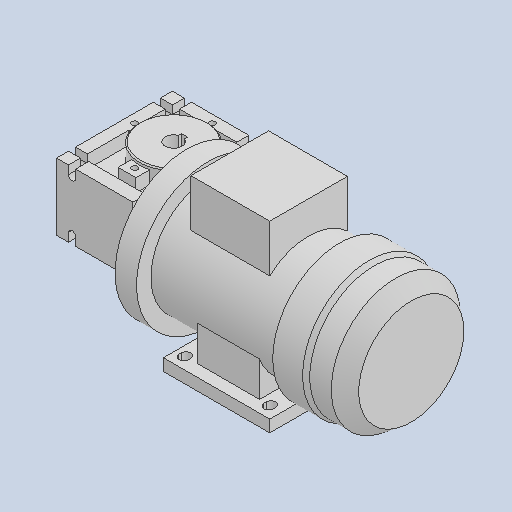
# Autodesk Inventor part: RDS-5005 Gear Motor
Saved by Autodesk Inventor 2026.2 (Build 302298000, 298)
## iProperties
Created: 2024-04-02
Part Number: RDS-5005 Gear Motor
Material: Типовые
Document SubType Name: Modeling
Designer: pokla
Density: 1 g/cm^3
Appearance: По умолчанию
Stock Number: Мотор-редуктор (СДР 060 2.0)
Author: pokla
Autodesk Inventor part; units mm, degrees
ref_plane "YZ Plane" through (0, 0, 0) normal (1, 0, 0) x (0, 1, 0)
sketch "Эскиз1" plane through (0, 0, 0) normal (0, 1, 0) x (-1, 0, 0)
  line L0 (0, 0) -> (0, -60)
  line L1 (0, -60) -> (-18, -60)
  line L2 (-18, -60) -> (-18, -48)
  line L3 (-18, -48) -> (-128, -48)
  line L4 (-128, -48) -> (-128, -56)
  line L5 (-128, -56) -> (-153, -56)
  line L6 (-175, -54) -> (-188, -44)
  line L7 (-188, -44) -> (-188, 0)
  line L8 (-188, 0) -> (0, 0)
  line L9 (-153, -56) -> (-157, -54)
  line L10 (-157, -54) -> (-175, -54)
  point P0 (-9, -60)
  dimension "d0" = 188
  dimension "d1" = 18
  dimension "d2" = 12
  dimension "d3" = 110
  dimension "d4" = 25
  dimension "d6" = 2
  dimension "d7" = 4
  dimension "d8" = 18
  dimension "d10" = 10
  dimension "d13" = 8
  dimension "d14" = 120
  constraints: 22 end point, 6 perpendicular, 1 horizontal, 1 midpoint, 1 parallel, 1 vertical
  measures "d0" distance of L7.end L0.start
  measures "d1" distance of L0.end L1.end
  measures "d2" distance of L1.end L2.end
  measures "d3" distance of L2.end L3.end
  measures "d4" distance of L4.end L5.end
  measures "d6" vertical distance of L5.end L9.end
  measures "d7" horizontal distance of L5.end L9.end
  measures "d8" distance of L9.end L6.start
  measures "d10" vertical distance of L6.start L6.end
  measures "d13" distance of L3.end L4.end
  measures "d14" diameter of point (-9, -60) L8
revolve "Вращение1" add sketch "Эскиз1" angle 360 about axis through (188, 0, 0) along (-1, 0, 0)
sketch "Эскиз2" plane through (0, 0, 0) normal (0, 1, 0) x (-1, 0, 0)
  line L0 (-18, -48) -> (-18, 48) projected
  line L1 (-128, -48) -> (-128, 48) projected
  line L2 (-54, -45) -> (-106, -45)
  line L3 (-106, -45) -> (-106, 45)
  line L4 (-106, 45) -> (-54, 45)
  line L5 (-54, 45) -> (-54, -45)
  point P0 (0, 0)
  point P1 (-54, 0)
  point P2 (-18, 0)
  dimension "d16" = 52
  dimension "d17" = 90
  dimension "d18" = 36
  constraints: 8 end point, 2 midpoint, 2 parallel, 1 horizontal, 1 horizontal alignment, 1 perpendicular
  measures "d16" distance of L3.end L4.end
  measures "d17" distance of L2.end L3.end
  measures "d18" distance between parallel lines of L5 L0
extrude "Выдавливание1" add sketch "Эскиз2" against normal blind 46
sketch "Эскиз3" plane through (0, -46, 0) normal (0, -1, 0) x (1, 0, 0)
  line L0 (35.5, 55) -> (124.5, 55)
  line L1 (124.5, 55) -> (124.5, -55)
  line L2 (124.5, -55) -> (35.5, -55)
  line L3 (35.5, -55) -> (35.5, 55)
  line L4 (54, -45) -> (106, -45) projected
  point P0 (0, 0)
  point P1 (124.5, 0)
  point P2 (80, -55)
  point P3 (80, -45)
  dimension "d21" = 89
  dimension "d22" = 110
  constraints: 8 end point, 3 midpoint, 2 parallel, 1 horizontal, 1 horizontal alignment, 1 perpendicular, 1 vertical alignment
  measures "d21" distance of L1.end L2.end
  measures "d22" distance of L0.end L1.end
extrude "Выдавливание2" add sketch "Эскиз3" along normal blind 10
sketch "Эскиз4" plane through (0, -56, 0) normal (0, -1, 0) x (1, 0, 0)
  line L0 (43.5, 46) -> (43.5, 44) construction
  line L1 (39.5, 46) -> (39.5, 44)
  line L2 (47.5, 44) -> (47.5, 46)
  arc A0 (47.5, 46) -> (39.5, 46) centre (43.5, 46) ccw
  arc A1 (39.5, 44) -> (47.5, 44) centre (43.5, 44) ccw
  line L3 (35.5, 55) -> (35.5, -55) projected
  line L4 (124.5, 55) -> (35.5, 55) projected
  point P0 (0, 0)
  point P1 (43.5, 45)
  point P2 (43.5, 40)
  point P3 (43.5, 50)
  point P4 (47.5, 45)
  point P5 (39.5, 45)
  dimension "d25" = 12
  dimension "d27" = 10
  dimension "d28" = 15
  dimension "d29" = 8
  constraints: 8 end point, 6 point on circle, 4 tangent, 3 midpoint, 2 centre point, 1 parallel
  measures "d25" distance between parallel lines of L3 L2
  measures "d27" distance of point (43.5, 40) point (43.5, 50)
  measures "d28" distance from line of L4 point (43.5, 40)
  measures "d29" distance of point (47.5, 45) point (39.5, 45)
extrude "Выдавливание3" cut sketch "Эскиз4" against normal blind 10
pattern_linear "Прямоуг.массив1" count 2 spacing 90 along (0, 0, -1) count 2 spacing 71 along (1, 0, 0) of "Выдавливание3"
sketch "Эскиз5" plane through (0, 0, 0) normal (0, 1, 0) x (-1, 0, 0)
  line L0 (-128, -48) -> (-128, 48) projected
  line L1 (-18, -48) -> (-18, 48) projected
  line L2 (-54, -13.7113) -> (-35.5, -13.7113) projected
  line L3 (-35.5, -13.7113) -> (-35.5, 13.7113) projected
  line L4 (-35.5, 13.7113) -> (-54, 13.7113) projected
  line L5 (-54, 13.7113) -> (-54, 45) projected
  line L6 (-54, 45) -> (-106, 45) projected
  line L7 (-106, 45) -> (-106, 13.7113) projected
  line L8 (-106, 13.7113) -> (-124.5, 13.7113) projected
  line L9 (-124.5, 13.7113) -> (-124.5, -13.7113) projected
  line L10 (-124.5, -13.7113) -> (-106, -13.7113) projected
  line L11 (-106, -13.7113) -> (-106, -45) projected
  line L12 (-106, -45) -> (-54, -45) projected
  line L13 (-54, -45) -> (-54, -13.7113) projected
  line L14 (-36, -32.5) -> (-102, -32.5)
  line L15 (-102, -32.5) -> (-102, 32.5)
  line L16 (-102, 32.5) -> (-36, 32.5)
  line L17 (-36, 32.5) -> (-36, -32.5)
  point P0 (0, 0)
  point P1 (-36, 0)
  point P2 (-18, 0)
  dimension "d38" = 66
  dimension "d39" = 65
  dimension "d40" = 18
  constraints: 8 end point, 2 midpoint, 2 parallel, 1 horizontal, 1 horizontal alignment, 1 perpendicular
  measures "d38" distance of L15.end L16.end
  measures "d39" distance of L14.end L15.end
  measures "d40" distance between parallel lines of L1 L17
extrude "Выдавливание4" add sketch "Эскиз5" along normal blind 75 contours L13 L14 L15 L16 L5 L4 L17 L2 | L2 L17 L14 L13 | L4 L5 L16 L17
sketch "Эскиз6" plane through (0, 0, 0) normal (1, 0, 0) x (0, 1, 0)
  line L0 (-28, 29) -> (-28, -68)
  line L1 (-28, -68) -> (28, -68)
  line L2 (28, -68) -> (28, 29)
  line L3 (28, 29) -> (-28, 29)
  line L4 (0, 0) -> (0, 234.4488) construction
  line L5 (0, 0) -> (0, -194.3934) construction
  point P0 (0, 29)
  point P1 (0, -68)
  dimension "d45" = 97
  dimension "d46" = 56
  dimension "d47" = 180
  dimension "d48" = 29
  constraints: 12 end point, 2 midpoint, 2 parallel, 2 point on line, 1 perpendicular, 1 vertical
  measures "d45" distance of L0.start L0.end
  measures "d46" distance of L1.end L0.end
  measures "d47" angle of L4 L5
  measures "d48" distance of L4.start point (0, 29)
extrude "Выдавливание5" add sketch "Эскиз6" against normal blind 80
ref_plane "РабПлоскость1" through (-80, -28, -19.5) normal (0, 0, -1) x (1, 0, 0)
sketch "Эскиз7" plane through (-80, -28, -68) normal (0, 0, -1) x (1, 0, 0)
  line L0 (80, 0) -> (80, -56) projected
  line L1 (80, 0) -> (0, 0) projected
  line L2 (0, -56) -> (0, 0) projected
  line L3 (80, -56) -> (0, -56) projected
  line L4 (10, 0) -> (10, -7)
  arc A0 (10, -7) -> (16, -7) centre (13, -7) ccw
  line L5 (16, -7) -> (16, 0)
  line L6 (80, -56) -> (0, -56) projected
  line L7 (40, 0) -> (40, -56) construction
  line L8 (0, -28) -> (80, -28) construction
  line L9 (80, 32) -> (80, -88) construction
  line L10 (70, 0) -> (70, -7)
  arc A1 (64, -7) -> (70, -7) centre (67, -7) ccw
  line L11 (64, -7) -> (64, 0)
  line L12 (10, -56) -> (10, -49)
  arc A2 (16, -49) -> (10, -49) centre (13, -49) ccw
  line L13 (16, -49) -> (16, -56)
  line L14 (70, -56) -> (70, -49)
  arc A3 (70, -49) -> (64, -49) centre (67, -49) ccw
  line L15 (64, -49) -> (64, -56)
  point P0 (13, -10)
  point P1 (67, -10)
  point P2 (13, -46)
  point P3 (67, -46)
  point P4 (16, -56)
  point P5 (64, 0)
  dimension "d51" = 6
  dimension "d52" = 10
  dimension "d53" = 10
  constraints: 20 end point, 18 symmetric about line, 9 point on circle, 4 centre point, 3 midpoint, 3 perpendicular, 2 point on line, 2 tangent, 3 other
  measures "d51" distance between parallel lines of L5 L4
  measures "d52" distance from line of L1 point (13, -10)
  measures "d53" distance between parallel lines of L2 L4
extrude "Выдавливание6" cut sketch "Эскиз7" against normal blind 11 contours L10 A1 L11 L1 | L3 L15 A3 L14 | L5 A0 L4 L1 | L3 L12 A2 L13
sketch "Эскиз8" plane through (-80, 0, 0) normal (-1, 0, 0) x (0, 0, 1)
  line L0 (-68, 28) -> (-68, -28) projected
  line L1 (-68, -28) -> (29, -28) projected
  line L2 (29, -28) -> (29, 28) projected
  line L3 (29, 28) -> (-68, 28) projected
  line L4 (-58, -28) -> (-58, -21)
  arc A0 (-52, -21) -> (-58, -21) centre (-55, -21) ccw
  line L5 (-52, -21) -> (-52, -28)
  line L6 (-68, 0) -> (29, 0) construction
  line L7 (-19.5, 28) -> (-19.5, -28) construction
  line L8 (-58, 28) -> (-58, 21)
  arc A1 (-58, 21) -> (-52, 21) centre (-55, 21) ccw
  line L9 (-52, 21) -> (-52, 28)
  line L10 (19, -28) -> (19, -21)
  arc A2 (19, -21) -> (13, -21) centre (16, -21) ccw
  line L11 (13, -21) -> (13, -28)
  line L12 (19, 28) -> (19, 21)
  arc A3 (13, 21) -> (19, 21) centre (16, 21) ccw
  line L13 (13, 21) -> (13, 28)
  point P0 (0, 0)
  point P1 (-55, -18)
  point P2 (-55, 18)
  point P3 (16, -18)
  point P4 (16, 18)
  point P5 (19, 28)
  point P6 (13, 28)
  point P7 (-52, 28)
  point P8 (-58, 28)
  point P9 (13, -28)
  point P10 (19, -28)
  dimension "d56" = 10
  dimension "d57" = 6
  dimension "d58" = 10
  constraints: 20 end point, 18 symmetric about line, 9 point on circle, 4 centre point, 4 midpoint, 2 perpendicular, 2 point on line, 2 tangent, 3 other
  measures "d56" distance between parallel lines of L0 L4
  measures "d57" distance between parallel lines of L4 L5
  measures "d58" distance from line of L1 point (-55, -18)
extrude "Выдавливание7" cut sketch "Эскиз8" against normal blind 11 contours L3 L9 A1 L8 | L4 A0 L5 L1 | L3 L12 A3 L13 | L11 A2 L10 L1
mirror "Зеркальное отражение1" about plane through (-80, -28, -19.5) normal (0, 0, -1) of "Выдавливание6"
sketch "Эскиз9" plane through (0, 0, 0) normal (1, 0, 0) x (0, 0, -1)
  line L0 (58, -28) -> (58, -21) projected
  arc A0 (58, -21) -> (52, -21) centre (55, -21) ccw projected
  line L1 (52, -21) -> (52, -28) projected
  line L2 (58, 21) -> (58, 28) projected
  arc A1 (52, 21) -> (58, 21) centre (55, 21) ccw projected
  line L3 (52, 28) -> (52, 21) projected
  line L4 (58, -28) -> (52, -28)
  line L5 (68, -28) -> (57, -28) projected
  line L6 (52, 28) -> (52, 21) projected
  line L7 (58, 28) -> (52, 28)
  point P0 (0, 0)
  constraints: 4 end point, 1 collinear, 1 perpendicular
extrude "Выдавливание8" cut sketch "Эскиз9" against normal blind 11
sketch "Эскиз10" plane through (-64, -28, -68) normal (0, -1, 0) x (1, 0, 0)
  circle A0 centre (24, 39) radius 7
  line L0 (48, 97) -> (0, 97) construction
  line L1 (24, 97) -> (24, 0) construction
  line L2 (48, 0) -> (0, 0) construction
  line L3 (48, 97) -> (0, 97) construction
  line L4 (48, 0) -> (0, 0) construction
  point P0 (64, 68)
  point P1 (24, 97)
  point P2 (24, 0)
  dimension "d63" = 14
  dimension "d64" = 39
  constraints: 4 midpoint, 2 end point, 1 centre point, 1 vertical alignment
  measures "d63" diameter of A0
  measures "d64" distance of point (24, 0) A0.centre
extrude "Выдавливание9" cut sketch "Эскиз10" against normal up to surface (56 mm away)
sketch "Эскиз11" plane through (-64, -28, -68) normal (0, -1, 0) x (1, 0, 0)
  circle A0 centre (24, 39) radius 7 projected
  circle A1 centre (24, 39) radius 28.5
  point P0 (64, 68)
  dimension "d67" = 57
  constraints: 1 centre point, 1 coincident
  measures "d67" diameter of A1
extrude "Выдавливание10" add sketch "Эскиз11" along normal blind 3
sketch "Эскиз12" plane through (-64, -28, -68) normal (0, -1, 0) x (1, 0, 0)
  circle A0 centre (24, 39) radius 28.5 projected
  circle A1 centre (24, 39) radius 28.5 projected
  line L0 (53, 11) -> (53, 16) projected
  line L1 (53, 16) -> (64, 16) projected
  line L2 (64, 97) -> (64, 16) projected
  line L3 (64, 97) -> (54, 97) projected
  line L4 (54, 97) -> (54, 86) projected
  line L5 (54, 86) -> (48, 86) projected
  line L6 (48, 86) -> (48, 97) projected
  line L7 (48, 97) -> (0, 97) projected
  line L8 (0, 97) -> (0, 86) projected
  line L9 (0, 86) -> (-5, 86) projected
  line L10 (-5, 86) -> (-5, 81) projected
  line L11 (-5, 81) -> (-16, 81) projected
  line L12 (-16, 16) -> (-16, 81) projected
  line L13 (-16, 16) -> (-5, 16) projected
  line L14 (-5, 16) -> (-5, 11) projected
  line L15 (-5, 11) -> (0, 11) projected
  line L16 (0, 11) -> (0, 0) projected
  line L17 (48, 0) -> (0, 0) projected
  line L18 (48, 0) -> (48, 11) projected
  line L19 (48, 11) -> (53, 11) projected
  line L20 (31.5, 78) -> (31.5, 0)
  line L21 (31.5, 0) -> (16.5, 0)
  line L22 (16.5, 0) -> (16.5, 78)
  line L23 (16.5, 78) -> (31.5, 78)
  line L24 (31.5, 78) -> (16.5, 0) construction
  line L25 (31.5, 0) -> (16.5, 78) construction
  line L26 (24, 78) -> (24, 0) construction
  line L27 (64, 31.5) -> (-16, 31.5)
  line L28 (-16, 31.5) -> (-16, 46.5)
  line L29 (-16, 46.5) -> (64, 46.5)
  line L30 (64, 46.5) -> (64, 31.5)
  line L31 (64, 31.5) -> (-16, 46.5) construction
  line L32 (-16, 31.5) -> (64, 46.5) construction
  line L33 (64, 39) -> (-16, 39) construction
  line L34 (-6, 87) -> (-16, 87) projected
  line L35 (-6, 87) -> (-6, 10)
  line L36 (54, 10) -> (53, 11) projected
  line L37 (-6, 10) -> (54, 10)
  line L38 (54, 10) -> (54, 86)
  line L39 (54, 86) -> (-6, 86)
  point P0 (64, 68)
  point P1 (24, 39)
  point P2 (24, 39)
  point P3 (0, 10)
  point P4 (16.5, 10)
  point P5 (16.5, 11.5045)
  point P6 (-3.4955, 31.5)
  point P7 (-6, 31.5)
  point P8 (-6, 16)
  point P9 (54, 16)
  point P10 (54, 31.5)
  point P11 (51.4955, 31.5)
  point P12 (31.5, 11.5045)
  point P13 (31.5, 10)
  point P14 (48, 10)
  point P15 (31.5, 66.4955)
  point P16 (51.4955, 46.5)
  point P17 (54, 46.5)
  point P18 (48, 86)
  point P19 (0, 86)
  point P20 (-6, 81)
  point P21 (-6, 46.5)
  point P22 (-3.4955, 46.5)
  point P23 (16.5, 66.4955)
  dimension "d72" = 78
  dimension "d73" = 15
  dimension "d74" = 80
  dimension "d75" = 15
  constraints: 36 end point, 7 midpoint, 5 perpendicular, 4 parallel, 1 coincident, 1 horizontal, 1 point on line, 1 vertical, 1 other
  measures "d72" distance of L20.start L20.end
  measures "d73" distance of L20.end L21.end
  measures "d74" distance of L27.start L27.end
  measures "d75" distance of L27.end L28.end
extrude "Выдавливание11" cut sketch "Эскиз12" against normal blind 11 contours A0 L20 L23 L22 L29 L35 L11 L10 L9 L39 L5 L38 | L27 L38 L1 L0 L19 L18 L37 L20 A0 | L22 L37 L16 L15 L14 L13 L35 L27 A0
ref_plane "РабПлоскость2" through (-64, 0, 29) normal (0, -1, 0) x (1, 0, 0)
chamfer "Фаска1" distance 1 angle 45 1 edges at (-68.5, -31, -29)
mirror "Зеркальное отражение2" about plane through (-64, 0, 29) normal (0, -1, 0) of "Выдавливание11", "Выдавливание10", "Фаска1"
sketch "Эскиз13" plane through (-40, -31, -29) normal (0, -1, 0) x (-1, 0, 0)
  circle A0 centre (0, 0) radius 7 projected
  line L0 (2.5, 9) -> (2.5, 6.5383)
  circle A1 centre (0, 0) radius 7 projected
  line L1 (-2.5, 9) -> (-2.5, 6.5383)
  line L2 (2.5, 9) -> (-2.5, 9)
  point P0 (-40, -29)
  point P1 (0, 9)
  point P2 (-2.5, 6.5383)
  point P3 (2.5, 6.5383)
  dimension "d84" = 5
  dimension "d90" = 9
  dimension "d91" = 2.4617
  constraints: 6 end point, 2 point on circle, 2 vertical, 1 horizontal, 1 midpoint
  measures "d84" distance of L0.start L1.start
  measures "d90" distance of A0.centre point (0, 9)
  measures "d91" distance of L0.start L0.end
extrude "Выдавливание12" cut sketch "Эскиз13" against normal through all contours A0 L1 L2 L0
sketch "Эскиз14" plane through (-40, -28, -29) normal (0, -1, 0) x (1, 0, 0)
  line L0 (7.5, 27.4955) -> (7.5, 39) projected
  line L1 (7.5, 39) -> (-7.5, 39) projected
  line L2 (-7.5, 39) -> (-7.5, 27.4955) projected
  arc A0 (7.5, 27.4955) -> (-7.5, 27.4955) centre (0, 0) ccw projected
  line L3 (7.5, 39) -> (-7.5, 39) projected
  circle A1 centre (0, 32.5) radius 2.5
  circle A2 centre (-32.5, 0) radius 2.5
  circle A3 centre (0, -32.5) radius 2.5
  circle A4 centre (32.5, 0) radius 2.5
  point P0 (40, 29)
  point P1 (0, 39)
  dimension "d94" = 5
  dimension "d95" = 32.5
  dimension "d98" = 360
  dimension "d100" = 39
  constraints: 4 centre point, 1 midpoint, 9 other
  measures "d94" diameter of A1
  measures "d95" distance of A1.centre A0.centre
  measures "d100" distance from line of A4.centre L1
extrude "Выдавливание13" cut sketch "Эскиз14" against normal through all contours A1 | A2 | A3 | A4
equation "\"d30\" = d27"
equation "\"d47\" = Reductor_angle"
equation "\"Reductor_angle\" = 180deg"
